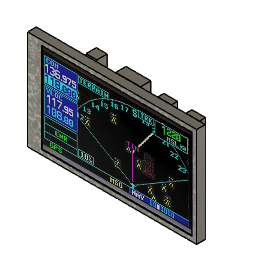
GNS 430 v16 (Autodesk Fusion 360 archive; units mm, degrees)
design "GNS 430_Monitor"
Autodesk Fusion 360 part; units mm, degrees
sketch "Sketch1" plane through (0, 0, 0) normal (0, -1, 0) x (1, 0, 0)
  line L0 (-49.3, 29.025) -> (49.3, 29.025)
  line L1 (49.3, 29.025) -> (49.3, -29.025)
  line L2 (49.3, -29.025) -> (-49.3, -29.025)
  line L3 (-49.3, -29.025) -> (-49.3, 29.025)
  line L4 (-49.3, 29.025) -> (49.3, -29.025) construction
  line L5 (49.3, 29.025) -> (-49.3, -29.025) construction
  line L6 (-41.3, 26.275) -> (46.55, 26.275)
  line L7 (46.55, 26.275) -> (46.55, -26.275)
  line L8 (46.55, -26.275) -> (-41.3, -26.275)
  line L9 (-41.3, -26.275) -> (-41.3, 26.275)
  line L10 (44.6638, -22.86) -> (-39.1562, -22.86)
  line L11 (-39.1562, -22.86) -> (-39.1562, 22.86)
  line L12 (-39.1562, 22.86) -> (44.6638, 22.86)
  line L13 (44.6638, 22.86) -> (44.6638, -22.86)
  line L14 (44.6638, -22.86) -> (-39.1562, 22.86) construction
  line L15 (-39.1562, -22.86) -> (44.6638, 22.86) construction
  point P0 (2.7538, 0)
  dimension "d81" = 98.6
  dimension "d82" = 58.05
  dimension "d1" = 8
  dimension "d2" = 2.75
  dimension "d3" = 2.75
  dimension "d4" = 2.75
  dimension "d8" = 83.82
  dimension "d9" = 45.72
  constraint horizontal L0
  constraint perpendicular L0 L1
  constraint parallel L0 L2
  constraint parallel L1 L3
  constraint coincident L4 origin
  constraint coincident L5 origin
  constraint horizontal L6
  constraint vertical L7
  constraint horizontal L8
  constraint vertical L9
  constraint horizontal L10
  constraint perpendicular L10 L11
  constraint parallel L10 L12
  constraint parallel L11 L13
  constraint coincident L14 P0
  constraint coincident L15 P0
  constraint horizontal origin P0
  measures "d81" distance of L1.end L2.end
  measures "d82" distance of L0.end L1.end
  measures "d1" distance of L3 L9
  measures "d2" distance of L1 L7
  measures "d3" distance of L0 L6
  measures "d4" distance of L2 L8
  measures "d8" distance of L11.end L12.end
  measures "d9" distance of L10.start L12.end
extrude "Extrude1" add sketch "Sketch1" along normal blind 5 contours L0 L1 L2 L3 | L6 L7 L8 L9 | L10 L11 L12 L13
extrude "Extrude2" cut sketch "Sketch1" against normal blind 0.5 from surface at 5 contours L6 L7 L8 L9 | L10 L11 L12 L13
sketch "Back Parts" plane through (0, 0, 0) normal (0, 1, 0) x (-1, 0, 0)
  line L0 (-49.3, -29.025) -> (49.3, -29.025)
  line L1 (49.3, -29.025) -> (49.3, 29.025)
  line L2 (49.3, 29.025) -> (-49.3, 29.025)
  line L3 (-49.3, 29.025) -> (-49.3, -29.025)
  line L4 (2.94, 17.2459) -> (-11.56, 17.2459)
  line L5 (-11.56, 17.2459) -> (-11.56, 29.2459)
  line L6 (-11.56, 29.2459) -> (2.94, 29.2459)
  line L7 (2.94, 29.2459) -> (2.94, 17.2459)
  line L8 (20.275, 30.0656) -> (13.925, 30.0656)
  line L9 (13.925, 30.0656) -> (13.925, 16.0656)
  line L10 (13.925, 16.0656) -> (20.275, 16.0656)
  line L11 (20.275, 16.0656) -> (20.275, 30.0656)
  line L12 (-46.01, 29.1238) -> (-38.01, 29.1238)
  line L13 (-38.01, 29.1238) -> (-38.01, 26.1238)
  line L14 (-38.01, 26.1238) -> (-46.01, 26.1238)
  line L15 (-46.01, 26.1238) -> (-46.01, 29.1238)
  line L16 (-21.65, 29.1728) -> (-29.62, 29.1728)
  line L17 (-29.62, 29.1728) -> (-29.62, 24.1728)
  line L18 (-29.62, 24.1728) -> (-21.65, 24.1728)
  line L19 (-21.65, 24.1728) -> (-21.65, 29.1728)
  line L20 (-29.1, -21.275) -> (3.6, -21.275)
  line L21 (3.6, -21.275) -> (3.6, -26.575)
  line L22 (3.6, -26.575) -> (-29.1, -26.575)
  line L23 (-29.1, -26.575) -> (-29.1, -21.275)
  point P0 (17.1, 16.0656)
  point P1 (-42.01, 26.1238)
  dimension "d10" = 12
  dimension "d13" = 14
  dimension "d19" = 5
  dimension "d21" = 8
  dimension "d22" = 3
  dimension "d28" = 60.86
  dimension "d29" = 46.36
  dimension "d30" = 32.2
  dimension "d31" = 6.35
  dimension "d32" = 7.29
  dimension "d33" = 19.68
  dimension "d34" = 27.65
  dimension "d35" = 2.45
  dimension "d36" = 45.7
  dimension "d37" = 20.2
  dimension "d38" = 5.3
  constraint horizontal L4
  constraint vertical L5
  constraint horizontal L6
  constraint vertical L7
  constraint horizontal L8
  constraint vertical L9
  constraint horizontal L10
  constraint vertical L11
  constraint midpoint L10 P0
  constraint horizontal L12
  constraint vertical L13
  constraint vertical L15
  constraint horizontal L16
  constraint vertical L17
  constraint horizontal L18
  constraint vertical L19
  constraint midpoint L14 P1
  constraint coincident L7 L4.start
  constraint perpendicular L13 L14
  constraint horizontal L20
  constraint vertical L21
  constraint horizontal L22
  constraint vertical L23
  measures "d10" distance of L6.end L4.start
  measures "d13" distance of L8.start L10.end
  measures "d19" distance of L16.end L17.end
  measures "d21" distance of L12.start L12.end
  measures "d22" distance of L12.end L13.end
  measures "d28" distance of L1 L5
  measures "d29" distance of L1 L7
  measures "d30" distance of L1 P0
  measures "d31" distance of L9.end L10.end
  measures "d32" distance of L3 P1
  measures "d33" distance of L3 L17
  measures "d34" distance of L3 L19
  measures "d35" distance of L0 L22
  measures "d36" distance of L1 L21
  measures "d37" distance of L3 L23
  measures "d38" distance of L20.end L21.end
extrude "Extrude3" add sketch "Back Parts" along normal blind 6 contours L2 L9 L10 L11 | L2 L8 L9 L11 | L2 L4 L5 L7 | L2 L5 L6 L7
extrude "Extrude4" add sketch "Back Parts" along normal blind 3.5 contours L2 L12 L13 L15 | L2 L13 L14 L15 | L2 L16 L17 L19 | L2 L17 L18 L19
extrude "Extrude5" add sketch "Back Parts" along normal blind 13.5 contours L20 L21 L22 L23
equation "d8 = 3.3 \""
equation "d9 = 1.8 \""

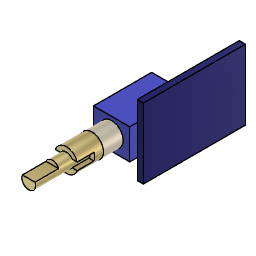
design "PropWashSim Dual Encoder (6mm screw, 6.5 loose)"
Autodesk Fusion 360 part; units mm, degrees
sketch "Profile" plane through (0, 0, 0) normal (0, 1, 0) x (1, 0, 0)
  line L0 (4.6, 3.85) -> (-4.6, 3.85)
  line L1 (-4.6, 3.85) -> (-4.6, -3.85)
  line L2 (-4.6, -3.85) -> (4.6, -3.85)
  line L3 (4.6, -3.85) -> (4.6, 3.85)
  line L4 (4.6, 3.85) -> (-4.6, -3.85) construction
  line L5 (-4.6, 3.85) -> (4.6, -3.85) construction
  circle A0 centre (0, 0) radius 2.925
  line L6 (2.235, -1.8869) -> (2.235, 1.8869)
  line L7 (0, 0) -> (0, 6.159) construction
  line L8 (-2.235, -1.8869) -> (-2.235, 1.8869)
  line L9 (-2.7664, -0.95) -> (2.7664, -0.95)
  line L10 (0, 0) -> (1.3963, 0) construction
  line L11 (-2.7664, 0.95) -> (2.7664, 0.95)
  dimension "d1" = 9.2
  dimension "d2" = 7.7
  dimension "d3" = 5.85
  dimension "d17" = 2.235
  dimension "d18" = 0.95
  constraint horizontal L0
  constraint perpendicular L0 L1
  constraint parallel L0 L2
  constraint parallel L1 L3
  constraint coincident L4 A0.centre
  constraint coincident L5 A0.centre
  constraint coincident A0.centre L7.start
  constraint coincident A0 L6.start
  constraint vertical L6
  constraint coincident A0 L6.end
  constraint vertical L7
  constraint symmetric L6.start L7 L8.start
  constraint symmetric L6.end L7 L8.end
  constraint coincident A0 L9.start
  constraint coincident A0 L9.end
  constraint horizontal L9
  constraint perpendicular L7 L10
  constraint symmetric L9.start L10 L11.start
  constraint symmetric L9.end L10 L11.end
  measures "d1" distance of L1.end L2.end
  measures "d2" distance of L0.end L1.end
  measures "d3" diameter of A0
  measures "d17" distance of A0.centre L6
  measures "d18" distance of A0.centre L9
extrude "Extrude1" add sketch "Profile" along normal blind 14.75 contours L0 L1 L2 L3 | A0 L6 L9 L11 | A0 L6 L11 | A0 L6 L9 | A0 L6 L8 L11 | L6 L8 L9 L11 | A0 L6 L8 L9 | A0 L8 L11 | A0 L8 L9 L11 | A0 L8 L9 makes body 1
extrude "Extrude2" add sketch "Profile" against normal blind 5 contours A0 L6 L9 L11 | A0 L6 L11 | A0 L6 L9 | A0 L6 L8 L11 | L6 L8 L9 L11 | A0 L6 L8 L9 | A0 L8 L11 | A0 L8 L9 L11 | A0 L8 L9 bodies 1
extrude "Extrude3" add sketch "Profile" against normal blind 6.5 from surface at -5 separate body contours A0 L6 L11 | A0 L6 L9 | A0 L6 L8 L11 | A0 L6 L8 L9 | A0 L8 L11 | A0 L8 L9 makes body 2 at (1.1749, -9.3333, -2.6787) makes body 3 at (-1.1749, -9.3333, 2.6787)
extrude "Extrude5" add sketch "Profile" against normal blind 2.25 from surface at -5 separate body contours A0 L6 L9 L11 | L6 L8 L9 L11 | A0 L8 L9 L11 makes body 4
combine "Combine1" operation add target body 3 tool bodies 4 2
cylinder "CylinderPrimitive1" add diameter 3.5 height 9.55 placed x (1, 0, 0) y (0, 0, 1) z (0, -1, 0) at (0, -11.5, 0) bodies 3
sketch "PCB" plane through (4.6, 0, 0) normal (1, 0, 0) x (0, 1, 0)
  line L0 (0, 3.85) -> (0, -3.85)
  line L1 (0, -3.85) -> (14.75, -3.85)
  line L2 (14.75, -3.85) -> (14.75, 3.85)
  line L3 (14.75, 3.85) -> (0, 3.85)
  line L4 (27.8, 8.9) -> (1.9, 8.9)
  line L5 (1.9, 8.9) -> (1.9, -8.9)
  line L6 (1.9, -8.9) -> (27.8, -8.9)
  line L7 (27.8, -8.9) -> (27.8, 8.9)
  line L8 (27.8, 8.9) -> (1.9, -8.9) construction
  line L9 (1.9, 8.9) -> (27.8, -8.9) construction
  point P0 (14.85, 0)
  dimension "d12" = 25.9
  dimension "d13" = 17.8
  dimension "d14" = 1.9
  constraint horizontal L4
  constraint perpendicular L4 L5
  constraint parallel L4 L6
  constraint parallel L5 L7
  constraint coincident L8 P0
  constraint coincident L9 P0
  constraint horizontal origin P0
  measures "d12" distance of L5.end L6.end
  measures "d13" distance of L4.end L5.end
  measures "d14" distance of origin L5
extrude "Extrude4" add sketch "PCB" along normal blind 1.55 separate body contours L1 L2 L3 L4 L5 L6 L7 | L1 L2 L3 L5 makes body 5
extrude "Extrude6" add 1 faces at (-0.4497, -11.5, 0.2434) along direction (0, 1, 0) up to surface (4.25 mm away) on bodies 3 bodies 3
sketch "Sketch4" plane through (0, -21.05, 0) normal (0, -1, 0) x (1, 0, 0)
  circle A0 centre (0, 0) radius 1.75
  line L0 (-1.6039, 0.7) -> (1.6039, 0.7)
  dimension "d25" = 2.45
  constraint coincident A0 L0.start
  constraint coincident A0 L0.end
  constraint horizontal L0
extrude "Extrude7" cut sketch "Sketch4" against normal blind 6 contours A0 L0 picked at (-0.2322, 1.2474) bodies 3
equation "d17 = ( 4.47 / 2 ) * 1 mm"
equation "d18 = ( 1.9 / 2 ) * 1 mm"
